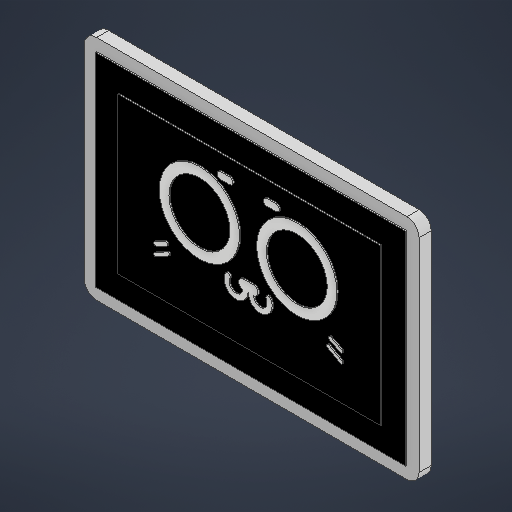
# Autodesk Inventor part: screen
Saved by Autodesk Inventor 2025.2 (Build 292293000, 293)
## iProperties
Created: 2025-01-18
Part Number: screen
Material: Generic
Document SubType Name: Modeling
Designer: user
Density: 1 g/cm^3
Appearance: Default
Author: user
Autodesk Inventor part; units mm, degrees
ref_plane "YZ Plane" through (0, 0, 0) normal (1, 0, 0) x (0, 1, 0)
ref_plane "XZ Plane" through (0, 0, 0) normal (0, 1, 0) x (-1, 0, 0)
ref_plane "XY Plane" through (0, 0, 0) normal (0, 0, 1) x (1, 0, 0)
sketch "Sketch1" plane through (0, 0, 0) normal (0, 0, 1) x (1, 0, 0)
  line L0 (-3.4332, 10.582) -> (251.5668, 10.582)
  line L1 (261.5668, 0.582) -> (261.5668, -166.418)
  line L2 (251.5668, -176.418) -> (-3.4332, -176.418)
  line L3 (-13.4332, -166.418) -> (-13.4332, 0.582)
  arc A0 (-3.4332, 10.582) -> (-13.4332, 0.582) centre (-3.4332, 0.582) ccw
  arc A1 (261.5668, 0.582) -> (251.5668, 10.582) centre (251.5668, 0.582) ccw
  arc A2 (251.5668, -176.418) -> (261.5668, -166.418) centre (251.5668, -166.418) ccw
  arc A3 (-13.4332, -166.418) -> (-3.4332, -176.418) centre (-3.4332, -166.418) ccw
  point P0 (0, 0)
  point P1 (261.5668, -176.418)
  point P2 (261.5668, 10.582)
  point P3 (-13.4332, -176.418)
  dimension "d0" = 275
  dimension "d1" = 187
  dimension "d2" = 10
  dimension "d3" = 10
  constraints: 8 end point, 8 point on circle, 8 tangent, 6 point on line, 4 centre point, 2 equal radius, 2 parallel, 1 horizontal, 1 perpendicular
  measures "d0" distance of point (261.567, -176.418) point (-13.433, -176.418)
  measures "d1" distance of point (261.567, 10.582) point (261.567, -176.418)
  measures "d2" radius of A0
  measures "d3" radius of A3
extrude "Extrusion1" add sketch "Sketch1" along normal blind 10
sketch "Sketch2" plane through (0, 0, 10) normal (0, 0, 1) x (1, 0, 0)
  line L0 (-3.4332, -176.418) -> (251.5668, -176.418) projected
  arc A0 (251.5668, -176.418) -> (261.5668, -166.418) centre (251.5668, -166.418) ccw projected
  line L1 (261.5668, -166.418) -> (261.5668, 0.582) projected
  arc A1 (261.5668, 0.582) -> (251.5668, 10.582) centre (251.5668, 0.582) ccw projected
  line L2 (251.5668, 10.582) -> (-3.4332, 10.582) projected
  arc A2 (-3.4332, 10.582) -> (-13.4332, 0.582) centre (-3.4332, 0.582) ccw projected
  line L3 (-13.4332, 0.582) -> (-13.4332, -166.418) projected
  arc A3 (-13.4332, -166.418) -> (-3.4332, -176.418) centre (-3.4332, -166.418) ccw projected
  line L4 (-3.4332, -166.418) -> (-3.4332, 0.582)
  line L5 (-3.4332, 0.582) -> (251.5668, 0.582)
  line L6 (251.5668, 0.582) -> (251.5668, -166.418)
  line L7 (251.5668, -166.418) -> (-3.4332, -166.418)
  point P0 (0, 0)
  dimension "d6" = 10
  constraints: 8 end point, 3 other
  measures "d6" distance between parallel lines of L3 L4
extrude "Extrusion2" add sketch "Sketch2" along normal blind 1 contours L4 L5 L6 L7
sketch "Sketch3" plane through (0, 0, 10) normal (0, 0, 1) x (1, 0, 0)
  line L0 (-3.4332, -176.418) -> (251.5668, -176.418) projected
  arc A0 (-13.4332, -166.418) -> (-3.4332, -176.418) centre (-3.4332, -166.418) ccw projected
  line L1 (-13.4332, 0.582) -> (-13.4332, -166.418) projected
  line L2 (251.5668, -166.418) -> (-3.4332, -166.418) projected
  line L3 (-3.4332, -166.418) -> (-3.4332, 0.582) projected
  line L4 (-3.4332, 0.582) -> (251.5668, 0.582) projected
  line L5 (251.5668, 0.582) -> (251.5668, -166.418) projected
  line L6 (-3.4332, -176.418) -> (251.5668, -176.418) projected
  arc A1 (251.5668, -176.418) -> (261.5668, -166.418) centre (251.5668, -166.418) ccw projected
  line L7 (261.5668, -166.418) -> (261.5668, 0.582) projected
  arc A2 (261.5668, 0.582) -> (251.5668, 10.582) centre (251.5668, 0.582) ccw projected
  line L8 (251.5668, 10.582) -> (-3.4332, 10.582) projected
  arc A3 (-3.4332, 10.582) -> (-13.4332, 0.582) centre (-3.4332, 0.582) ccw projected
  line L9 (-13.4332, 0.582) -> (-13.4332, -166.418) projected
  arc A4 (-13.4332, -166.418) -> (-3.4332, -176.418) centre (-3.4332, -166.418) ccw projected
  line L10 (16.0668, -18.918) -> (232.0668, -18.918)
  line L11 (232.0668, -18.918) -> (232.0668, -146.918)
  line L12 (232.0668, -146.918) -> (16.0668, -146.918)
  line L13 (16.0668, -146.918) -> (16.0668, -18.918)
  point P0 (0, 0)
  dimension "d9" = 29.5
  constraints: 8 end point, 3 other
  measures "d9" distance between parallel lines of L8 L10
extrude "Extrusion3" add sketch "Sketch3" along normal blind 2 contours L10 L11 L12 L13
sketch "Sketch4" plane through (0, 0, 12) normal (0, 0, 1) x (1, 0, 0)
  line L0 (16.0668, -146.918) -> (16.0668, -18.918) projected
  line L1 (16.0668, -82.918) -> (232.0668, -82.918)
  line L2 (232.0668, -18.918) -> (232.0668, -146.918) projected
  line L3 (16.0668, -18.918) -> (232.0668, -18.918) projected
  line L4 (124.0668, -18.918) -> (124.0668, -146.918)
  line L5 (232.0668, -146.918) -> (16.0668, -146.918) projected
  circle A0 centre (84.0668, -68.918) radius 25
  circle A1 centre (164.0668, -68.918) radius 25
  circle A2 centre (84.0668, -68.918) radius 33
  circle A3 centre (164.0668, -68.918) radius 33
  arc A4 (137.7003, -84.5497) -> (135.2314, -86.6386) centre (136.4659, -85.5941) ccw
  arc A5 (107.3599, -101.918) -> (120.7737, -101.918) centre (114.0668, -105.6575) ccw construction
  arc A6 (105.493, -100.8771) -> (122.6406, -100.8771) centre (114.0668, -105.6575) ccw
  arc A7 (109.2267, -102.9589) -> (118.9069, -102.9589) centre (114.0668, -105.6575) ccw
  arc A8 (109.2267, -102.9589) -> (105.493, -100.8771) centre (107.3599, -101.918) ccw
  arc A9 (122.6406, -100.8771) -> (118.9069, -102.9589) centre (120.7737, -101.918) ccw
  arc A10 (127.3599, -101.918) -> (140.7737, -101.918) centre (134.0668, -105.6575) ccw construction
  arc A11 (125.493, -100.8771) -> (142.6406, -100.8771) centre (134.0668, -105.6575) ccw
  arc A12 (129.2267, -102.9589) -> (138.9069, -102.9589) centre (134.0668, -105.6575) ccw
  arc A13 (142.6406, -100.8771) -> (138.9069, -102.9589) centre (140.7737, -101.918) ccw
  arc A14 (129.2267, -102.9589) -> (125.493, -100.8771) centre (127.3599, -101.918) ccw
  line L6 (116.2728, -101.918) -> (132.2286, -101.918) construction
  line L7 (120.2123, -105.8575) -> (128.2891, -105.8575)
  line L8 (128.2891, -97.9785) -> (120.2123, -97.9785)
  arc A15 (120.2123, -97.9785) -> (120.2123, -105.8575) centre (120.2123, -101.918) ccw
  arc A16 (128.2891, -105.8575) -> (128.2891, -97.9785) centre (128.2891, -101.918) ccw
  line L9 (46.5888, -109.7271) -> (57.9275, -104.0578) construction
  line L10 (48.473, -110.3552) -> (57.2994, -105.942)
  line L11 (56.0433, -103.4297) -> (47.2169, -107.8429)
  arc A17 (47.2169, -107.8429) -> (48.473, -110.3552) centre (47.8449, -109.0991) ccw
  arc A18 (57.2994, -105.942) -> (56.0433, -103.4297) centre (56.6714, -104.6858) ccw
  line L12 (46.5888, -117.6089) -> (59.506, -110.3552) construction
  line L13 (48.4113, -118.1206) -> (58.9943, -112.1776)
  line L14 (57.6836, -109.8435) -> (47.1005, -115.7864)
  arc A19 (47.1005, -115.7864) -> (48.4113, -118.1206) centre (47.7559, -116.9535) ccw
  arc A20 (58.9943, -112.1776) -> (57.6836, -109.8435) centre (58.339, -111.0105) ccw
  line L15 (201.5448, -109.7271) -> (190.2061, -104.0578) construction
  line L16 (199.6606, -110.3552) -> (190.8342, -105.942)
  line L17 (192.0903, -103.4297) -> (200.9167, -107.8429)
  arc A21 (199.6606, -110.3552) -> (200.9167, -107.8429) centre (200.2886, -109.0991) ccw
  arc A22 (192.0903, -103.4297) -> (190.8342, -105.942) centre (191.4622, -104.6858) ccw
  line L18 (201.5448, -117.6089) -> (188.6276, -110.3552) construction
  line L19 (199.7223, -118.1206) -> (189.1393, -112.1776)
  line L20 (190.45, -109.8435) -> (201.0331, -115.7864)
  arc A23 (199.7223, -118.1206) -> (201.0331, -115.7864) centre (200.3777, -116.9535) ccw
  arc A24 (190.45, -109.8435) -> (189.1393, -112.1776) centre (189.7946, -111.0105) ccw
  line L21 (98.4484, -33.7823) -> (111.5633, -33.7823) construction
  line L22 (101.2587, -36.5926) -> (108.7529, -36.5926)
  line L23 (108.7529, -30.972) -> (101.2587, -30.972)
  arc A25 (101.2587, -30.972) -> (101.2587, -36.5926) centre (101.2587, -33.7823) ccw
  arc A26 (108.7529, -36.5926) -> (108.7529, -30.972) centre (108.7529, -33.7823) ccw
  line L24 (149.6852, -33.7823) -> (136.5703, -33.7823) construction
  line L25 (146.8749, -36.5926) -> (139.3806, -36.5926)
  line L26 (139.3806, -30.972) -> (146.8749, -30.972)
  arc A27 (146.8749, -36.5926) -> (146.8749, -30.972) centre (146.8749, -33.7823) ccw
  arc A28 (139.3806, -30.972) -> (139.3806, -36.5926) centre (139.3806, -33.7823) ccw
  point P0 (0, 0)
  point P1 (124.2507, -101.918)
  point P2 (52.2582, -106.8924)
  point P3 (53.0474, -113.982)
  point P4 (195.8754, -106.8924)
  point P5 (195.0862, -113.982)
  point P6 (105.0058, -33.7823)
  point P7 (143.1278, -33.7823)
  point P8 (123.8812, -105.8575)
  point P9 (124.2524, -105.8575)
  point P10 (128.5286, -105.8502)
  point P11 (119.6062, -105.8106)
  dimension "d12" = 50
  dimension "d13" = 40
  dimension "d14" = 8
  dimension "d15" = 8
  dimension "d16" = 50
  dimension "d18" = 10
  constraints: 64 point on circle, 60 end point, 35 symmetric about line, 29 centre point, 20 tangent, 14 point on line, 8 midpoint, 4 parallel, 2 horizontal, 12 other
  measures "d12" diameter of A0
  measures "d13" distance from line of L4 A0.centre
  measures "d14" radial gap between concentric circles of A0 A2
  measures "d15" radial gap between concentric circles of A1 A3
  measures "d16" distance from line of L3 A0.centre
  measures "d18" distance from line of A5.centre L4
extrude "Extrusion4" add sketch "Sketch4" along normal blind 1 contours A2 L1 A0 | L1 A0 A2 | L7 A6 A9 A7 A15 L8 L4 | L4 L8 A16 A12 A14 A11 L7 | L7 A15 A7 A9 A6 | A6 A8 A7 A15 L7 | L7 A16 A12 A13 A11 | A11 A14 A12 A16 L7 | A3 L1 A1 | L1 A1 A3 | A17 L11 A18 L10 | A19 L14 A20 L13 | L16 A22 L17 A21 | L19 A24 L20 A23 | A25 L23 A26 L22 | L25 A28 L26 A27
body "Solid1"
